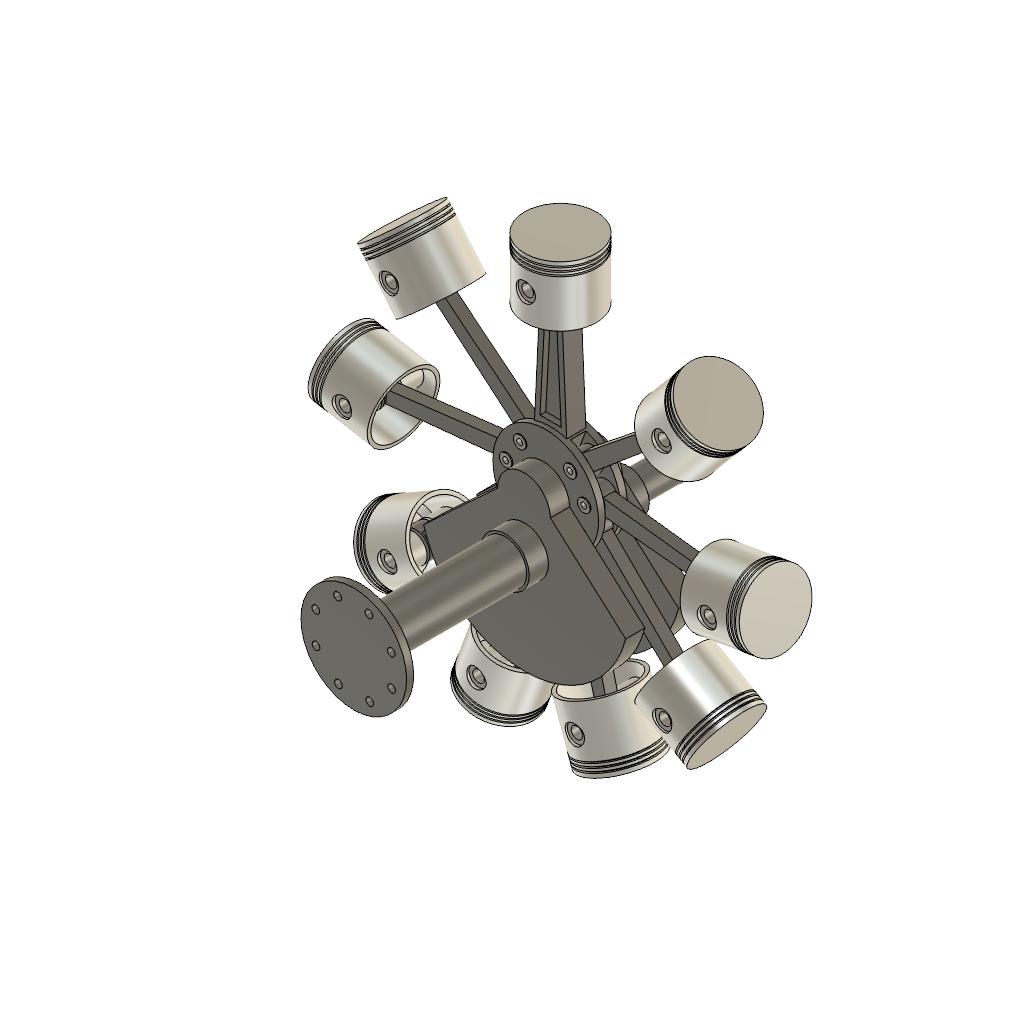
R9 Engine Assembly (Autodesk Fusion 360 design; units mm, degrees)
part number: 2026-10-17-19-55-54-126
part number: 2026-10-17-20-31-18-906
part number: 2026-10-17-20-31-41-189
part number: 2026-10-17-20-32-00-717
part number: 2026-10-17-20-32-24-134
part number: 2026-10-17-20-32-48-420
part number: 2026-10-17-20-32-48-693
part number: 2026-10-17-20-32-48-947
part number: 2026-10-17-20-32-49-015
Autodesk Fusion 360 part; units mm, degrees
note: some values were not read from the file. Set by a fixed rule: which sketch regions a step uses.
sketch "Cylinder blank sketch" plane through (0, 0, 0) normal (0, 1, 0) x (1, 0, 0) in component "Cylinder"
  line L0 (0, -240) -> (82, -240)
  line L1 (82, -240) -> (82, -262)
  line L2 (82, -262) -> (108, -262)
  line L3 (108, -262) -> (108, -274)
  line L4 (108, -274) -> (82, -280)
  line L5 (82, -280) -> (82, -533)
  line L6 (82, -533) -> (90, -539)
  line L7 (90, -539) -> (60, -631)
  arc A0 (0, -641) -> (60, -631) centre (-0.6, -452.4) ccw
  line L8 (0, -641) -> (0, -240)
revolve "Cylinder blank" add sketch "Cylinder blank sketch" angle 360 about axis through (0, 0, 1.75) along (0, 0, 1) makes body 1 in component "Cylinder"
sketch "Barrel fin sketch" plane through (0, 0, 0) normal (0, 1, 0) x (1, 0, 0) in component "Cylinder"
  line L0 (80, -290) -> (118, -290)
  line L1 (118, -290) -> (118, -292.2)
  line L2 (118, -292.2) -> (80, -292.2)
  line L3 (80, -292.2) -> (80, -290)
revolve "Barrel fin" add sketch "Barrel fin sketch" angle 360 about axis through (0, 0, 1.75) along (0, 0, 1) bodies 1 in component "Cylinder"
pattern_linear "Barrel fin pattern" count 34 spacing 7 along (0, 0, 1) count 3 spacing 0 along (0, 0, 1) of "Barrel fin" in component "Cylinder"
sketch "Head fin sketch" plane through (0, 0, 0) normal (0, 1, 0) x (1, 0, 0) in component "Cylinder"
  line L0 (40, -545) -> (112, -545)
  line L1 (112, -545) -> (112, -547.5)
  line L2 (112, -547.5) -> (40, -547.5)
  line L3 (40, -547.5) -> (40, -545)
revolve "Head fin" add sketch "Head fin sketch" angle 360 about axis through (0, 0, 1.75) along (0, 0, 1) bodies 1 in component "Cylinder"
pattern_linear "Head fin pattern" count 12 spacing 7.5 along (0, 0, 1) count 3 spacing 0 along (0, 0, 1) of "Head fin" in component "Cylinder"
sketch "Port bosses sketch" plane through (0, 0, 0) normal (0, 1, 0) x (1, 0, 0) in component "Cylinder"
  circle A0 centre (0, -565) radius 26
extrude "Port bosses" add sketch "Port bosses sketch" along normal mid plane 250 bodies 1 in component "Cylinder"
ref_plane "WorkPlane1" through (0, 0, 632) normal (0, 0, 1) x (1, 0, 0) in component "Cylinder"
sketch "Rocker boxes" plane through (0, 0, 632) normal (0, 0, 1) x (1, 0, 0) in component "Cylinder"
  circle A0 centre (0, -42) radius 19
  circle A1 centre (0, 42) radius 19
  dimension "d318" = 38
  dimension "d319" = 38
  measures "d318" diameter of A0
  measures "d319" diameter of A1
extrude "Rocker box, exhaust side" add sketch "Rocker boxes" along normal blind 34 contours A0 bodies 1 in component "Cylinder"
extrude "Rocker box, intake side" add sketch "Rocker boxes" along normal blind 34 contours A1 bodies 1 in component "Cylinder"
ref_plane "WorkPlane2" through (0, 0, 240) normal (0, 0, 1) x (1, 0, 0) in component "Cylinder"
sketch "Bore sketch" plane through (0, 0, 240) normal (0, 0, 1) x (1, 0, 0) in component "Cylinder"
  circle A0 centre (0, 0) radius 75
  dimension "d326" = 150
  constraint coincident A0.centre origin
  measures "d326" diameter of A0
extrude "Bore" cut sketch "Bore sketch" along normal blind 297 bodies 1 in component "Cylinder"
sketch "Combustion chamber sketch" plane through (0, 0, 0) normal (0, 1, 0) x (1, 0, 0) in component "Cylinder"
  line L0 (0, -537) -> (75, -537)
  line L1 (0, -585) -> (0, -537)
  arc A0 (0, -585) -> (75, -537) centre (0, -502.4063) ccw
  dimension "d329" = 75
  dimension "d330" = 48
  measures "d329" horizontal distance of L0.start L0.end
  measures "d330" vertical distance of L0.start L1.start
revolve "Combustion chamber" cut sketch "Combustion chamber sketch" angle 360 about axis through (0, 0, 1.75) along (0, 0, 1) bodies 1 in component "Cylinder"
sketch "Port bores sketch" plane through (0, 0, 0) normal (0, 1, 0) x (1, 0, 0) in component "Cylinder"
  circle A0 centre (0, -565) radius 20
  dimension "d332" = 40
  measures "d332" diameter of A0
extrude "Port bores" cut sketch "Port bores sketch" along normal mid plane 260 bodies 1 in component "Cylinder"
sketch "Inter-cylinder clearance" plane through (0, 0, 0) normal (0, 1, 0) x (1, 0, 0) in component "Cylinder"
  line L0 (66.5246, -188.6226) -> (258.0559, -714.8504)
  line L1 (258.0559, -714.8504) -> (558.0559, -714.8504)
  line L2 (558.0559, -714.8504) -> (366.5246, -188.6226)
  line L3 (366.5246, -188.6226) -> (66.5246, -188.6226)
  line L4 (-66.5246, -188.6226) -> (-258.0559, -714.8504)
  line L5 (-258.0559, -714.8504) -> (-558.0559, -714.8504)
  line L6 (-558.0559, -714.8504) -> (-366.5246, -188.6226)
  line L7 (-366.5246, -188.6226) -> (-66.5246, -188.6226)
extrude "Fin clearance" cut sketch "Inter-cylinder clearance" along normal mid plane 400 bodies 1 in component "Cylinder"
sketch "Main case section" plane through (0, 0, 0) normal (0, 1, 0) x (1, 0, 0) in component "Crankcase"
  line L0 (95.3602, -262) -> (241.4605, -139.4073)
  line L1 (241.4605, -139.4073) -> (274.5788, 48.4156)
  line L2 (274.5788, 48.4156) -> (179.2186, 213.5844)
  line L3 (179.2186, 213.5844) -> (0, 278.8146)
  line L4 (0, 278.8146) -> (-179.2186, 213.5844)
  line L5 (-179.2186, 213.5844) -> (-274.5788, 48.4156)
  line L6 (-274.5788, 48.4156) -> (-241.4605, -139.4073)
  line L7 (-241.4605, -139.4073) -> (-95.3602, -262)
  line L8 (-95.3602, -262) -> (95.3602, -262)
extrude "Main case" add sketch "Main case section" along normal mid plane 230 separate body makes body 2 in component "Crankcase"
sketch "Nose case section" plane through (0, 0, 0) normal (0, 0, 1) x (1, 0, 0) in component "Crankcase"
  line L0 (46, -115) -> (240, -115)
  line L1 (240, -115) -> (205, -165)
  line L2 (205, -165) -> (140, -235)
  line L3 (140, -235) -> (112, -262)
  line L4 (112, -262) -> (46, -262)
  line L5 (46, -262) -> (46, -115)
revolve "Nose case" add sketch "Nose case section" angle 360 about axis through (0, 1.75, 0) along (0, 1, 0) bodies 2 in component "Crankcase"
sketch "Rear case section" plane through (0, 0, 0) normal (0, 0, 1) x (1, 0, 0) in component "Crankcase"
  line L0 (46, 115) -> (230, 115)
  line L1 (230, 115) -> (230, 178)
  line L2 (230, 178) -> (202, 205)
  line L3 (202, 205) -> (46, 205)
  line L4 (46, 205) -> (46, 115)
revolve "Rear case" add sketch "Rear case section" angle 360 about axis through (0, 1.75, 0) along (0, 1, 0) bodies 2 in component "Crankcase"
sketch "Crank cavity sketch" plane through (0, 0, 0) normal (0, 1, 0) x (1, 0, 0) in component "Crankcase"
  circle A0 centre (0, 0) radius 235
  dimension "d341" = 470
  constraint coincident A0.centre origin
  measures "d341" diameter of A0
extrude "Crank cavity" cut sketch "Crank cavity sketch" along normal mid plane 160 bodies 2 in component "Crankcase"
sketch "Main bearing housing sketch" plane through (0, 0, 0) normal (0, 1, 0) x (1, 0, 0) in component "Crankcase"
  circle A0 centre (0, 0) radius 51
  dimension "d344" = 102
  constraint coincident A0.centre origin
  measures "d344" diameter of A0
extrude "Main bearing housing" cut sketch "Main bearing housing sketch" along normal mid plane 600 bodies 2 in component "Crankcase"
ref_plane "WorkPlane1" through (0, 0, 200) normal (0, 0, 1) x (1, 0, 0) in component "Crankcase"
sketch "Cylinder spigot bore sketch" plane through (0, 0, 200) normal (0, 0, 1) x (1, 0, 0) in component "Crankcase"
  circle A0 centre (0, 0) radius 83
  dimension "d349" = 166
  constraint coincident A0.centre origin
  measures "d349" diameter of A0
extrude "Cylinder spigot bore" cut sketch "Cylinder spigot bore sketch" along normal blind 90 bodies 2 in component "Crankcase"
pattern_circular "Spigot bore pattern" count 9 over 360 about axis through (0, 1.75, 0) along (0, 1, 0) of "Cylinder spigot bore" in component "Crankcase"
ref_plane "WorkPlane2" through (0, 215, 0) normal (0, 1, 0) x (0, 0, 1) in component "Crankcase"
sketch "Engine mount pad sketch" plane through (0, 215, 0) normal (0, 1, 0) x (1, 0, 0) in component "Crankcase"
  circle A0 centre (56.4333, -155.0493) radius 20
  circle A1 centre (56.4333, -155.0493) radius 8
  dimension "d356" = 40
  dimension "d357" = 16
  measures "d356" diameter of A0
  measures "d357" diameter of A1
extrude "Engine mount pad" add sketch "Engine mount pad sketch" along normal mid plane 20 bodies 2 in component "Crankcase"
pattern_circular "Mount pad pattern" count 9 over 360 about axis through (0, 1.75, 0) along (0, 1, 0) of "Engine mount pad" in component "Crankcase"
sketch "Nose gear chamber section" plane through (0, 0, 0) normal (0, 0, 1) x (1, 0, 0) in component "Crankcase"
  line L0 (62, -118) -> (226, -118)
  line L1 (226, -118) -> (194, -162)
  line L2 (194, -162) -> (130, -226)
  line L3 (130, -226) -> (62, -226)
  line L4 (62, -226) -> (62, -118)
revolve "Nose gear chamber" cut sketch "Nose gear chamber section" angle 360 about axis through (0, 1.75, 0) along (0, 1, 0) bodies 2 in component "Crankcase"
sketch "Accessory drive chamber section" plane through (0, 0, 0) normal (0, 0, 1) x (1, 0, 0) in component "Crankcase"
  line L0 (62, 118) -> (216, 118)
  line L1 (216, 118) -> (216, 174)
  line L2 (216, 174) -> (192, 193)
  line L3 (192, 193) -> (62, 193)
  line L4 (62, 193) -> (62, 118)
revolve "Accessory drive chamber" cut sketch "Accessory drive chamber section" angle 360 about axis through (0, 1.75, 0) along (0, 1, 0) bodies 2 in component "Crankcase"
sketch "Crank web profile" plane through (0, 0, 0) normal (0, 1, 0) x (1, 0, 0) in component "Crankshaft"
  line L0 (0, 0) -> (0, -85) construction
  arc A0 (-55, -85) -> (55, -85) centre (0, -85) ccw
  line L1 (55, -85) -> (-55, -85) construction
  arc A1 (210.0889, 56.2931) -> (-210.0889, 56.2931) centre (0, 0) ccw
  line L2 (0, 0) -> (210.0889, 56.2931) construction
  line L3 (55, -85) -> (210.0889, 56.2931)
  line L4 (-55, -85) -> (-210.0889, 56.2931)
  dimension "d364" = 85
  dimension "d365" = 55
  dimension "d366" = 217.5
  dimension "d367" = 105
  constraint vertical L0
  constraint coincident L0.end A0.centre
  constraint horizontal L1
  constraint coincident L0.start A1.centre
  constraint symmetric L0 A1.start A1.end
  measures "d364" distance of L0.start L0.end
  measures "d365" radius of A0
  measures "d366" radius of A1
  measures "d367" angle of L0 L2
extrude "Crank webs" add sketch "Crank web profile" along normal mid plane 150 separate body makes body 3 in component "Crankshaft"
sketch "Web gap sketch" plane through (0, 0, 0) normal (0, 1, 0) x (1, 0, 0) in component "Crankshaft"
  circle A0 centre (0, 0) radius 250
  constraint coincident A0.centre origin
extrude "Web gap" cut sketch "Web gap sketch" along normal mid plane 70 bodies 3 makes body 4 at (0, -75, -15.8333) in component "Crankshaft"
sketch "Crankpin sketch" plane through (0, 0, 0) normal (0, 1, 0) x (1, 0, 0) in component "Crankshaft"
  line L0 (0, 0) -> (0, -85) construction
  circle A0 centre (0, -85) radius 40
  circle A1 centre (0, -85) radius 20
  dimension "d372" = 85
  dimension "d373" = 80
  dimension "d374" = 40
  constraint vertical L0
  constraint coincident L0.end A0.centre
  constraint concentric A0 A1
  measures "d372" distance of L0.start L0.end
  measures "d373" diameter of A0
  measures "d374" diameter of A1
extrude "Crankpin" add sketch "Crankpin sketch" along normal mid plane 150 bodies 3 4 in component "Crankshaft"
sketch "Front main journal and propeller shaft section" plane through (0, 0, 0) normal (0, 0, 1) x (1, 0, 0) in component "Crankshaft"
  line L0 (0, -430) -> (110, -430)
  line L1 (110, -430) -> (110, -415)
  line L2 (110, -415) -> (45, -415)
  line L3 (45, -415) -> (45, -115)
  line L4 (45, -115) -> (50, -115)
  line L5 (50, -115) -> (50, -75)
  line L6 (50, -75) -> (0, -75)
  line L7 (0, -75) -> (0, -430)
revolve "Front main journal and propeller shaft" add sketch "Front main journal and propeller shaft section" angle 360 about axis through (0, 1.75, 0) along (0, 1, 0) bodies 3 in component "Crankshaft"
sketch "Rear main journal and accessory drive section" plane through (0, 0, 0) normal (0, 0, 1) x (1, 0, 0) in component "Crankshaft"
  line L0 (0, 75) -> (45, 75)
  line L1 (45, 75) -> (45, 140)
  line L2 (45, 140) -> (30, 140)
  line L3 (30, 140) -> (30, 230)
  line L4 (30, 230) -> (0, 230)
  line L5 (0, 230) -> (0, 75)
revolve "Rear main journal and accessory drive" add sketch "Rear main journal and accessory drive section" angle 360 about axis through (0, 1.75, 0) along (0, 1, 0) bodies 3 in component "Crankshaft"
ref_plane "WorkPlane1" through (0, -422.5, 0) normal (0, 1, 0) x (0, 0, 1) in component "Crankshaft"
sketch "Propeller bolt circle" plane through (0, -422.5, 0) normal (0, 1, 0) x (1, 0, 0) in component "Crankshaft"
  circle A0 centre (32.5281, -78.5298) radius 8
  circle A1 centre (78.5298, -32.5281) radius 8
  circle A2 centre (78.5298, 32.5281) radius 8
  circle A3 centre (32.5281, 78.5298) radius 8
  circle A4 centre (-32.5281, 78.5298) radius 8
  circle A5 centre (-78.5298, 32.5281) radius 8
  circle A6 centre (-78.5298, -32.5281) radius 8
  circle A7 centre (-32.5281, -78.5298) radius 8
  dimension "d381" = 16
  measures "d381" diameter of A0
extrude "Propeller bolt holes" cut sketch "Propeller bolt circle" along normal mid plane 20 bodies 3 in component "Crankshaft"
sketch "Big end sketch" plane through (0, 0, 0) normal (0, 1, 0) x (1, 0, 0) in component "Master Rod"
  circle A0 centre (0, -85) radius 110
  dimension "d384" = 220
  measures "d384" diameter of A0
extrude "Big end" add sketch "Big end sketch" along normal mid plane 60 separate body makes body 5 in component "Master Rod"
sketch "Shank sketch" plane through (0, 0, 0) normal (0, 1, 0) x (1, 0, 0) in component "Master Rod"
  line L0 (-34, -180) -> (34, -180)
  line L1 (34, -180) -> (22, -435)
  line L2 (22, -435) -> (-22, -435)
  line L3 (-22, -435) -> (-34, -180)
extrude "Shank" add sketch "Shank sketch" along normal mid plane 40 bodies 5 in component "Master Rod"
sketch "Small end sketch" plane through (0, 0, 0) normal (0, 1, 0) x (1, 0, 0) in component "Master Rod"
  circle A0 centre (0, -465) radius 35
  dimension "d389" = 70
  measures "d389" diameter of A0
extrude "Small end" add sketch "Small end sketch" along normal mid plane 40 bodies 5 in component "Master Rod"
ref_plane "WorkPlane1" through (0, 14, 0) normal (0, 1, 0) x (0, 0, 1) in component "Master Rod"
sketch "Shank flute front sketch" plane through (0, 14, 0) normal (0, 1, 0) x (1, 0, 0) in component "Master Rod"
  line L0 (-22, -205) -> (22, -205)
  line L1 (22, -205) -> (11, -415)
  line L2 (11, -415) -> (-11, -415)
  line L3 (-11, -415) -> (-22, -205)
extrude "Shank flute front" cut sketch "Shank flute front sketch" along normal mid plane 12 bodies 5 in component "Master Rod"
ref_plane "WorkPlane2" through (0, -14, 0) normal (0, 1, 0) x (0, 0, 1) in component "Master Rod"
sketch "Shank flute rear sketch" plane through (0, -14, 0) normal (0, 1, 0) x (1, 0, 0) in component "Master Rod"
  line L0 (-22, -205) -> (22, -205)
  line L1 (22, -205) -> (11, -415)
  line L2 (11, -415) -> (-11, -415)
  line L3 (-11, -415) -> (-22, -205)
extrude "Shank flute rear" cut sketch "Shank flute rear sketch" along normal mid plane 12 bodies 5 in component "Master Rod"
sketch "Link rod slot sketch" plane through (0, 0, 0) normal (0, 1, 0) x (1, 0, 0) in component "Master Rod"
  arc A0 (39.3323, -193.0647) -> (-39.3323, -193.0647) centre (0, -85) ccw
  arc A1 (18.4691, -135.7434) -> (-18.4691, -135.7434) centre (0, -85) ccw
  line L0 (39.3323, -193.0647) -> (18.4691, -135.7434)
  line L1 (-39.3323, -193.0647) -> (-18.4691, -135.7434)
  dimension "d400" = 115
  dimension "d401" = 54
  constraint concentric A0 A1
  measures "d400" radius of A0
  measures "d401" radius of A1
extrude "Link rod slot" cut sketch "Link rod slot sketch" along normal mid plane 32 bodies 5 in component "Master Rod"
sketch "Pin layout" plane through (0, 0, 0) normal (0, 1, 0) x (1, 0, 0) in component "Master Rod"
  line L0 (0, 0) -> (0, -85) construction
  line L1 (0, -85) -> (0, -465) construction
  circle A0 centre (0, -85) radius 40.5
  circle A1 centre (0, -465) radius 20
  line L2 (0, -85) -> (52.0972, -147.1136) construction
  circle A2 centre (52.0972, -147.1136) radius 13
  line L3 (0, -85) -> (81.2759, -99.7267) construction
  circle A3 centre (81.2759, -99.7267) radius 13
  line L4 (0, -85) -> (71.6223, -45.0002) construction
  circle A4 centre (71.6223, -45.0002) radius 13
  line L5 (0, -85) -> (28.1952, -9.7927) construction
  circle A5 centre (28.1952, -9.7927) radius 13
  line L6 (0, -85) -> (-28.1952, -9.7927) construction
  circle A6 centre (-28.1952, -9.7927) radius 13
  line L7 (0, -85) -> (-71.6223, -45.0002) construction
  circle A7 centre (-71.6223, -45.0002) radius 13
  line L8 (0, -85) -> (-81.2759, -99.7267) construction
  circle A8 centre (-81.2759, -99.7267) radius 13
  line L9 (0, -85) -> (-52.0972, -147.1136) construction
  circle A9 centre (-52.0972, -147.1136) radius 13
  dimension "d404" = 85
  dimension "d405" = 380
  dimension "d406" = 81
  dimension "d407" = 40
  dimension "d408" = 81.0692
  dimension "d409" = 39.988
  dimension "d410" = 26
  dimension "d411" = 82.5993
  dimension "d412" = 79.73
  dimension "d413" = 26
  dimension "d414" = 82.035
  dimension "d415" = 119.183
  dimension "d416" = 26
  dimension "d417" = 80.3188
  dimension "d418" = 159.449
  dimension "d419" = 26
  dimension "d420" = 80.3188
  dimension "d421" = 159.449
  dimension "d422" = 26
  dimension "d423" = 82.035
  dimension "d424" = 119.183
  dimension "d425" = 26
  dimension "d426" = 82.5993
  dimension "d427" = 79.73
  dimension "d428" = 26
  dimension "d429" = 81.0692
  dimension "d430" = 39.988
  dimension "d431" = 26
  constraint vertical L0
  constraint vertical L1
  constraint coincident L0.end L1.start
  constraint coincident L1.end A1.centre
  constraint coincident L2.end A2.centre
  constraint coincident L3.end A3.centre
  constraint coincident L4.end A4.centre
  constraint coincident L5.end A5.centre
  constraint coincident L6.end A6.centre
  constraint coincident L7.end A7.centre
  constraint coincident L8.end A8.centre
  constraint coincident L9.end A9.centre
  measures "d404" distance of L0.start L0.end
  measures "d405" distance of L0.end L1.end
  measures "d406" diameter of A0
  measures "d407" diameter of A1
  measures "d408" distance of L0.end L2.end
  measures "d409" angle of L1 L2
  measures "d410" diameter of A2
  measures "d411" distance of L0.end L3.end
  measures "d412" angle of L1 L3
  measures "d413" diameter of A3
  measures "d414" distance of L0.end L4.end
  measures "d415" angle of L1 L4
  measures "d416" diameter of A4
  measures "d417" distance of L0.end L5.end
  measures "d418" angle of L1 L5
  measures "d419" diameter of A5
  measures "d420" distance of L0.end L6.end
  measures "d421" angle of L1 L6
  measures "d422" diameter of A6
  measures "d423" distance of L0.end L7.end
  measures "d424" angle of L1 L7
  measures "d425" diameter of A7
  measures "d426" distance of L0.end L8.end
  measures "d427" angle of L1 L8
  measures "d428" diameter of A8
  measures "d429" distance of L0.end L9.end
  measures "d430" angle of L1 L9
  measures "d431" diameter of A9
extrude "Crankpin, wrist pin and knuckle pin bores" cut sketch "Pin layout" along normal mid plane 80 bodies 5 in component "Master Rod"
sketch "Eyes sketch" plane through (0, 0, 0) normal (0, 1, 0) x (1, 0, 0) in component "Link Rod"
  circle A0 centre (0, 0) radius 24
  circle A1 centre (0, -300) radius 30
  dimension "d434" = 48
  dimension "d435" = 60
  constraint coincident A0.centre origin
  measures "d434" diameter of A0
  measures "d435" diameter of A1
extrude "Eyes" add sketch "Eyes sketch" along normal mid plane 30 separate body makes body 6 at (23.8807, 10, 2.3896) makes body 7 at (29.8509, 10, 302.987) in component "Link Rod"
sketch "Shank sketch (2)" plane through (0, 0, 0) normal (0, 1, 0) x (1, 0, 0) in component "Link Rod"
  line L0 (-16, -15) -> (16, -15)
  line L1 (16, -15) -> (13, -280)
  line L2 (13, -280) -> (-13, -280)
  line L3 (-13, -280) -> (-16, -15)
extrude "Shank'" add sketch "Shank sketch (2)" along normal mid plane 24 bodies 6 7 in component "Link Rod"
sketch "Pin layout (2)" plane through (0, 0, 0) normal (0, 1, 0) x (1, 0, 0) in component "Link Rod"
  line L0 (0, 0) -> (0, -300) construction
  circle A0 centre (0, 0) radius 13
  circle A1 centre (0, -300) radius 20
  dimension "d440" = 300
  dimension "d441" = 26
  dimension "d442" = 40
  constraint vertical L0
  constraint coincident L0.start A0.centre
  constraint coincident L0.end A1.centre
  measures "d440" distance of L0.start L0.end
  measures "d441" diameter of A0
  measures "d442" diameter of A1
extrude "Knuckle pin and wrist pin bores" cut sketch "Pin layout (2)" along normal mid plane 40 bodies 6 in component "Link Rod"
ref_plane "WorkPlane1" through (0, 0, -55) normal (0, 0, 1) x (1, 0, 0) in component "Piston"
sketch "Piston diameter" plane through (0, 0, -55) normal (0, 0, 1) x (1, 0, 0) in component "Piston"
  circle A0 centre (0, 0) radius 74.6
  dimension "d447" = 149.2
  constraint coincident A0.centre origin
  measures "d447" diameter of A0
extrude "Piston blank" add sketch "Piston diameter" along normal blind 125 separate body makes body 8 in component "Piston"
sketch "Underside sketch" plane through (0, 0, 0) normal (0, 1, 0) x (1, 0, 0) in component "Piston"
  line L0 (0, 56) -> (67, 56)
  line L1 (67, 56) -> (67, -40)
  line L2 (67, -40) -> (55, -50)
  line L3 (55, -50) -> (0, -50)
  line L4 (0, -50) -> (0, 56)
revolve "Underside" cut sketch "Underside sketch" angle 360 about axis through (0, 0, 1.75) along (0, 0, 1) bodies 8 in component "Piston"
sketch "Ring grooves sketch" plane through (0, 0, 0) normal (0, 1, 0) x (1, 0, 0) in component "Piston"
  line L0 (69.6, -59) -> (80, -59)
  line L1 (80, -59) -> (80, -62)
  line L2 (80, -62) -> (69.6, -62)
  line L3 (69.6, -62) -> (69.6, -59)
  line L4 (69.6, -51) -> (80, -51)
  line L5 (80, -51) -> (80, -54)
  line L6 (80, -54) -> (69.6, -54)
  line L7 (69.6, -54) -> (69.6, -51)
  line L8 (69.6, -43) -> (80, -43)
  line L9 (80, -43) -> (80, -46)
  line L10 (80, -46) -> (69.6, -46)
  line L11 (69.6, -46) -> (69.6, -43)
revolve "Ring grooves" cut sketch "Ring grooves sketch" angle 360 about axis through (0, 0, 1.75) along (0, 0, 1) bodies 8 in component "Piston"
sketch "Pin bosses sketch" plane through (0, 0, 0) normal (0, 1, 0) x (1, 0, 0) in component "Piston"
  circle A0 centre (0, 0) radius 30
  line L0 (-18, 0) -> (18, 0)
  line L1 (18, 0) -> (18, -52)
  line L2 (18, -52) -> (-18, -52)
  line L3 (-18, -52) -> (-18, 0)
extrude "Pin bosses" add sketch "Pin bosses sketch" along normal mid plane 132 bodies 8 in component "Piston"
sketch "Rod clearance sketch" plane through (0, 0, 0) normal (0, 1, 0) x (1, 0, 0) in component "Piston"
  line L0 (-40, 40) -> (40, 40)
  line L1 (40, 40) -> (40, -41)
  line L2 (40, -41) -> (-40, -41)
  line L3 (-40, -41) -> (-40, 40)
extrude "Rod clearance" cut sketch "Rod clearance sketch" along normal mid plane 42 bodies 8 in component "Piston"
sketch "Pin bore sketch" plane through (0, 0, 0) normal (0, 1, 0) x (1, 0, 0) in component "Piston"
  circle A0 centre (0, 0) radius 20
  dimension "d456" = 40
  constraint coincident A0.centre origin
  measures "d456" diameter of A0
extrude "Pin bore" cut sketch "Pin bore sketch" along normal mid plane 160 bodies 8 in component "Piston"
sketch "Section" plane through (0, 0, 0) normal (0, 1, 0) x (1, 0, 0) in component "Wrist Pin"
  circle A0 centre (0, 0) radius 20
  circle A1 centre (0, 0) radius 12
  dimension "d459" = 40
  dimension "d460" = 24
  constraint coincident A0.centre A1.centre
  constraint concentric A0 A1
  measures "d459" diameter of A0
  measures "d460" diameter of A1
extrude "Pin" add sketch "Section" along normal mid plane 136 separate body makes body 9 in component "Wrist Pin"
sketch "Section (2)" plane through (0, 0, 0) normal (0, 1, 0) x (1, 0, 0) in component "Knuckle Pin"
  circle A0 centre (0, 0) radius 13
  circle A1 centre (0, 0) radius 6
  dimension "d463" = 26
  dimension "d464" = 12
  constraint coincident A0.centre A1.centre
  constraint concentric A0 A1
  measures "d463" diameter of A0
  measures "d464" diameter of A1
extrude "Pin'" add sketch "Section (2)" along normal mid plane 64 separate body makes body 10 in component "Knuckle Pin"
component "Cylinder" placed x (1, 0, 0) y (0, 1, 0) z (0, 0, 1) at (0, 0, 0)
component "Crankcase" placed x (1, 0, 0) y (0, 1, 0) z (0, 0, 1) at (0, 0, 0)
component "Crankshaft" placed x (1, 0, 0) y (0, 1, 0) z (0, 0, 1) at (0, 0, 0)
component "Master Rod" placed x (1, 0, 0) y (0, 1, 0) z (0, 0, 1) at (0, 0, 0)
component "Link Rod" placed x (1, 0, 0) y (0, 1, 0) z (0, 0, 1) at (0, 0, 0)
component "Piston" placed x (1, 0, 0) y (0, 1, 0) z (0, 0, 1) at (0, 0, 0)
component "Wrist Pin" placed x (1, 0, 0) y (0, 1, 0) z (0, 0, 1) at (0, 0, 0)
component "Knuckle Pin" placed x (1, 0, 0) y (0, 1, 0) z (0, 0, 1) at (0, 0, 0)
component "Cylinder" placed x (1, 0, 0) y (0, 1, 0) z (0, 0, 1) at (0, 0, 0)
component "Cylinder" placed x (1, 0, 0) y (0, 1, 0) z (0, 0, 1) at (0, 0, 0)
component "Cylinder" placed x (1, 0, 0) y (0, 1, 0) z (0, 0, 1) at (0, 0, 0)
component "Cylinder" placed x (1, 0, 0) y (0, 1, 0) z (0, 0, 1) at (0, 0, 0)
component "Cylinder" placed x (1, 0, 0) y (0, 1, 0) z (0, 0, 1) at (0, 0, 0)
component "Cylinder" placed x (1, 0, 0) y (0, 1, 0) z (0, 0, 1) at (0, 0, 0)
component "Cylinder" placed x (1, 0, 0) y (0, 1, 0) z (0, 0, 1) at (0, 0, 0)
component "Cylinder" placed x (1, 0, 0) y (0, 1, 0) z (0, 0, 1) at (0, 0, 0)
component "Piston" placed x (1, 0, 0) y (0, 1, 0) z (0, 0, 1) at (0, 0, 0)
component "Piston" placed x (1, 0, 0) y (0, 1, 0) z (0, 0, 1) at (0, 0, 0)
component "Piston" placed x (1, 0, 0) y (0, 1, 0) z (0, 0, 1) at (0, 0, 0)
component "Piston" placed x (1, 0, 0) y (0, 1, 0) z (0, 0, 1) at (0, 0, 0)
component "Piston" placed x (1, 0, 0) y (0, 1, 0) z (0, 0, 1) at (0, 0, 0)
component "Piston" placed x (1, 0, 0) y (0, 1, 0) z (0, 0, 1) at (0, 0, 0)
component "Piston" placed x (1, 0, 0) y (0, 1, 0) z (0, 0, 1) at (0, 0, 0)
component "Piston" placed x (1, 0, 0) y (0, 1, 0) z (0, 0, 1) at (0, 0, 0)
component "Wrist Pin" placed x (1, 0, 0) y (0, 1, 0) z (0, 0, 1) at (0, 0, 0)
component "Wrist Pin" placed x (1, 0, 0) y (0, 1, 0) z (0, 0, 1) at (0, 0, 0)
component "Wrist Pin" placed x (1, 0, 0) y (0, 1, 0) z (0, 0, 1) at (0, 0, 0)
component "Wrist Pin" placed x (1, 0, 0) y (0, 1, 0) z (0, 0, 1) at (0, 0, 0)
component "Wrist Pin" placed x (1, 0, 0) y (0, 1, 0) z (0, 0, 1) at (0, 0, 0)
component "Wrist Pin" placed x (1, 0, 0) y (0, 1, 0) z (0, 0, 1) at (0, 0, 0)
component "Wrist Pin" placed x (1, 0, 0) y (0, 1, 0) z (0, 0, 1) at (0, 0, 0)
component "Wrist Pin" placed x (1, 0, 0) y (0, 1, 0) z (0, 0, 1) at (0, 0, 0)
component "Link Rod" placed x (1, 0, 0) y (0, 1, 0) z (0, 0, 1) at (0, 0, 0)
component "Link Rod" placed x (1, 0, 0) y (0, 1, 0) z (0, 0, 1) at (0, 0, 0)
component "Link Rod" placed x (1, 0, 0) y (0, 1, 0) z (0, 0, 1) at (0, 0, 0)
component "Link Rod" placed x (1, 0, 0) y (0, 1, 0) z (0, 0, 1) at (0, 0, 0)
component "Link Rod" placed x (1, 0, 0) y (0, 1, 0) z (0, 0, 1) at (0, 0, 0)
component "Link Rod" placed x (1, 0, 0) y (0, 1, 0) z (0, 0, 1) at (0, 0, 0)
component "Link Rod" placed x (1, 0, 0) y (0, 1, 0) z (0, 0, 1) at (0, 0, 0)
component "Knuckle Pin" placed x (1, 0, 0) y (0, 1, 0) z (0, 0, 1) at (0, 0, 0)
component "Knuckle Pin" placed x (1, 0, 0) y (0, 1, 0) z (0, 0, 1) at (0, 0, 0)
component "Knuckle Pin" placed x (1, 0, 0) y (0, 1, 0) z (0, 0, 1) at (0, 0, 0)
component "Knuckle Pin" placed x (1, 0, 0) y (0, 1, 0) z (0, 0, 1) at (0, 0, 0)
component "Knuckle Pin" placed x (1, 0, 0) y (0, 1, 0) z (0, 0, 1) at (0, 0, 0)
component "Knuckle Pin" placed x (1, 0, 0) y (0, 1, 0) z (0, 0, 1) at (0, 0, 0)
component "Knuckle Pin" placed x (1, 0, 0) y (0, 1, 0) z (0, 0, 1) at (0, 0, 0)
equation "Bore = 150 mm" comment "Cylinder bore"
equation "Stroke = 170 mm" comment "Layout - set by kinematic study"
equation "CrankThrow = Stroke / 2" comment "Crankpin offset from main axis"
equation "MasterRodLength = 380 mm" comment "Layout - crankpin to wrist pin, cylinder 1"
equation "KnucklePinRadius = 80 mm" comment "Nominal knuckle pin circle; individual pins tuned, see design notes"
equation "LinkRodLength = MasterRodLength - KnucklePinRadius" comment "Knuckle pin to wrist pin"
equation "CrankpinDia = 80 mm"
equation "WristPinDia = 40 mm"
equation "KnucklePinDia = 26 mm"
equation "CylinderCount = 9"
equation "CompressionHeight = 70 mm" comment "Wrist pin centre to piston crown"
equation "DeckHeight = CrankThrow + MasterRodLength + CompressionHeight + 2 mm" comment "Crank axis to top of bore; 2 mm crown clearance at TDC"
equation "ChamberHeight = 48 mm" comment "Spherical chamber above deck; gives CR 6.8:1"
equation "BigEndAllowance = 1 mm" comment "Diametral allowance for big-end bearing shell"
equation "PistonClearance = 0.8 mm" comment "Diametral, cold"
equation "CounterweightRadius = 217.50 mm" comment "Balances rotating mass plus N/2 x reciprocating mass per cylinder"
equation "CounterweightHalfAngle = 75 deg"
equation "FinPitch = 7 mm" comment "Barrel fins"
equation "BarrelFinCount = 34"
equation "HeadFinPitch = 7.5 mm"
equation "HeadFinCount = 12"
equation "d305 = BarrelFinCount"
equation "d307 = FinPitch"
equation "d310 = HeadFinCount"
equation "d312 = HeadFinPitch"
equation "d316 = DeckHeight + 95 mm"
equation "d326 = Bore"
equation "d327 = DeckHeight - 240 mm"
equation "d329 = Bore / 2"
equation "d330 = ChamberHeight"
equation "d352 = CylinderCount"
equation "d360 = CylinderCount"
equation "d364 = CrankThrow"
equation "d366 = CounterweightRadius"
equation "d367 = 180 deg - CounterweightHalfAngle"
equation "d372 = CrankThrow"
equation "d373 = CrankpinDia"
equation "d404 = CrankThrow"
equation "d405 = MasterRodLength"
equation "d406 = CrankpinDia + BigEndAllowance"
equation "d407 = WristPinDia"
equation "d410 = KnucklePinDia"
equation "d413 = KnucklePinDia"
equation "d416 = KnucklePinDia"
equation "d419 = KnucklePinDia"
equation "d422 = KnucklePinDia"
equation "d425 = KnucklePinDia"
equation "d428 = KnucklePinDia"
equation "d431 = KnucklePinDia"
equation "d440 = LinkRodLength"
equation "d441 = KnucklePinDia"
equation "d442 = WristPinDia"
equation "d447 = Bore - PistonClearance"
equation "d448 = CompressionHeight + 55 mm"
equation "d456 = WristPinDia"
equation "d459 = WristPinDia"
equation "d463 = KnucklePinDia"
named bodies: "Cylinder", "Crankcase", "Crankshaft", "Master Rod", "Link Rod", "Piston", "Wrist Pin", "Knuckle Pin"
